100000_P04_POD-SKELETON_CAD (Autodesk Fusion 360 design; units mm, degrees)
description: POD - SPACESHIP (FocusPod v2) skeleton | Pod hoàn chỉnh
part number: 100000
description: BASE | Đế / sàn
part number: 110000
description: WALL | Vách
part number: 210000
description: FRONT | Mặt trước
part number: 350000
description: FRONT - DOOR AND GLAZING | Cửa và kính | P04
part number: 360000
description: CEILING | Trần
part number: 410000
description: LINING | Lớp tiêu âm
part number: 510000
description: AIR | Thông gió
part number: 610000
description: ELECTRICAL | Điện
part number: 710000
description: INTERIOR | Nội thất
part number: 810000
description: L1 WALL - SIDE PANEL - LOWER - LH | W-SIDE-LO | P04
part number: 2026-10-31-22-06-28-096
description: L1-CASS LINING - CASSETTE - SIDE LOWER - L | L-CASS-SIDE-LO | P04
part number: 2026-10-31-22-06-28-225
description: L2 WALL - SIDE PANEL - UPPER - LH | W-SIDE-UP | P04
part number: 2026-10-31-22-06-28-370
description: L2-CASS LINING - CASSETTE - SIDE UPPER - L | L-CASS-SIDE-UP | P04
part number: 2026-10-31-22-06-28-531
description: R1 WALL - SIDE PANEL - LOWER - RH | W-SIDE-LO | P04
part number: 2026-10-31-22-06-28-711
description: R1-CASS LINING - CASSETTE - SIDE LOWER - R | L-CASS-SIDE-LO | P04
part number: 2026-10-31-22-06-28-902
description: R2 WALL - SIDE PANEL - UPPER - RH | W-SIDE-UP | P04
part number: 2026-10-31-22-06-29-130
description: R2-CASS LINING - CASSETTE - SIDE UPPER - R | L-CASS-SIDE-UP | P04
part number: 2026-10-31-22-06-29-380
description: B1 WALL - BACK PANEL - LOWER - B1 | W-BACK-LO | P04
part number: 2026-10-31-22-06-29-641
description: B1-CASS LINING - CASSETTE - BACK LOWER - B1 | L-CASS-BACK-LO | P04
part number: 2026-10-31-22-06-29-889
description: B2 WALL - BACK PANEL - LOWER - B2 | W-BACK-LO | P04
part number: 2026-10-31-22-06-30-154
description: B2-CASS LINING - CASSETTE - BACK LOWER - B2 | L-CASS-BACK-LO | P04
part number: 2026-10-31-22-06-30-456
description: B3 WALL - BACK PANEL - UPPER - B3 | W-BACK-UP | P04
part number: 2026-10-31-22-06-30-798
description: B3-CASS LINING - CASSETTE - BACK UPPER - B3 | L-CASS-BACK-UP | P04
part number: 2026-10-31-22-06-31-178
description: B4 WALL - BACK PANEL - UPPER - B4 | W-BACK-UP | P04
part number: 2026-10-31-22-06-31-579
description: B4-CASS LINING - CASSETTE - BACK UPPER - B4 | L-CASS-BACK-UP | P04
part number: 2026-10-31-22-06-32-006
description: C1 CEILING - HALF PANEL - C1 | C-HALF | P04
part number: 2026-10-31-22-06-32-419
description: C1-CASS LINING - CASSETTE - CEILING - C1 | L-CASS-HALF | P04
part number: 2026-10-31-22-06-32-893
description: C2 CEILING - HALF PANEL - C2 | C-HALF | P04
part number: 2026-10-31-22-06-33-783
description: C2-CASS LINING - CASSETTE - CEILING - C2 | L-CASS-HALF | P04
part number: 2026-10-31-22-06-34-218
description: BAND-BACK BASE - BASE BAND - BACK | B-BAND-BACK | P04
part number: 2026-10-31-22-06-35-068
description: KICK FRONT - DOOR KICK STRIP | D-40 | P04
part number: 2026-10-31-22-06-36-171
description: DL FRONT - DECOR BLOCK - LEFT (FACETED, v1 MEASURED) | F-DL | P04
part number: 2026-10-31-22-06-36-706
description: DT FRONT - DECOR BLOCK - TOP (FACETED, v1 MEASURED) | F-DT | P04
part number: 2026-10-31-22-06-38-220
description: DR FRONT - DECOR BLOCK - RIGHT (FACETED, v1 MEASURED) | F-DR | P04
part number: 2026-10-31-22-06-40-806
description: DOOR FRONT - DOOR LEAF GLASS 4+4 (TRAPEZOID, v1 MEASURED) | F-GLASS-DOOR | P04
part number: 2026-10-31-22-06-44-745
description: FIXED FRONT - FIXED GLASS 4+4 (PENTAGON, v1 MEASURED) | F-GLASS-FIXED | P04
part number: 2026-10-31-22-06-45-730
description: BAND-L BASE - BASE BAND - SIDE - LH | B-BAND-SIDE | P04
part number: 2026-10-31-22-06-46-926
description: BAND-FL BASE - BASE BAND - FRONT LEFT (FACETED, UNDER DL) | B-BAND-FRONT | P04
part number: 2026-10-31-22-06-47-718
description: BAND-FR BASE - BASE BAND - FRONT RIGHT (FACETED, UNDER THE FIXED GLASS AND DR) | B-BAND-FRONT | P04
part number: 2026-10-31-22-06-49-290
description: BAND-R BASE - BASE BAND - SIDE - RH | B-BAND-SIDE | P04
part number: 2026-10-31-22-06-50-542
Autodesk Fusion 360 part; units mm, degrees
(part 1 of 2)
ref_plane "WorkPlane1" through (0, 0, 112.26) normal (0, 0, 1) x (1, 0, 0) in component "L1 WALL - SIDE PANEL - LOWER - LH"
sketch "OUTLINE - L1" plane through (0, 0, 112.26) normal (0, 0, 1) x (1, 0, 0) in component "L1 WALL - SIDE PANEL - LOWER - LH"
  line L0 (-1250, -642.74) -> (-1204, -642.74)
  line L1 (-1204, -642.74) -> (-1204, 850)
  line L2 (-1204, 850) -> (-1250, 850)
  line L3 (-1250, 850) -> (-1250, -642.74)
  dimension "d68" = 46
  dimension "d69" = 1492.74
  dimension "d70" = 1250
  dimension "d71" = 642.74
  constraint horizontal L0
  constraint vertical L1
  constraint horizontal L2
  constraint vertical L3
  measures "d68" horizontal distance of L0.start L0.end
  measures "d69" vertical distance of L0.start L2.end
  measures "d70" horizontal distance of origin L0.start
  measures "d71" vertical distance of origin L0.start
extrude "EXTRUDE - L1 ENVELOPE" add sketch "OUTLINE - L1" along normal blind 1142.74 makes body 1 in component "L1 WALL - SIDE PANEL - LOWER - LH"
ref_plane "WorkPlane1" through (0, 0, 112.26) normal (0, 0, 1) x (1, 0, 0) in component "L1-CASS LINING - CASSETTE - SIDE LOWER - L"
sketch "OUTLINE - L1-CASS" plane through (0, 0, 112.26) normal (0, 0, 1) x (1, 0, 0) in component "L1-CASS LINING - CASSETTE - SIDE LOWER - L"
  line L0 (-1200, -645) -> (-1166, -645)
  line L1 (-1166, -645) -> (-1166, 800)
  line L2 (-1166, 800) -> (-1200, 800)
  line L3 (-1200, 800) -> (-1200, -645)
  dimension "d76" = 34
  dimension "d77" = 1445
  dimension "d78" = 1200
  dimension "d79" = 645
  constraint horizontal L0
  constraint vertical L1
  constraint horizontal L2
  constraint vertical L3
  measures "d76" horizontal distance of L0.start L0.end
  measures "d77" vertical distance of L0.start L2.end
  measures "d78" horizontal distance of origin L0.start
  measures "d79" vertical distance of origin L0.start
extrude "EXTRUDE - L1-CASS ENVELOPE" add sketch "OUTLINE - L1-CASS" along normal blind 1142.74 separate body makes body 2 in component "L1-CASS LINING - CASSETTE - SIDE LOWER - L"
ref_plane "WorkPlane1" through (0, 0, 1257.26) normal (0, 0, 1) x (1, 0, 0) in component "L2 WALL - SIDE PANEL - UPPER - LH"
sketch "OUTLINE - L2" plane through (0, 0, 1257.26) normal (0, 0, 1) x (1, 0, 0) in component "L2 WALL - SIDE PANEL - UPPER - LH"
  line L0 (-1250, -642.74) -> (-1204, -642.74)
  line L1 (-1204, -642.74) -> (-1204, 850)
  line L2 (-1204, 850) -> (-1250, 850)
  line L3 (-1250, 850) -> (-1250, -642.74)
  dimension "d84" = 46
  dimension "d85" = 1492.74
  dimension "d86" = 1250
  dimension "d87" = 642.74
  constraint horizontal L0
  constraint vertical L1
  constraint horizontal L2
  constraint vertical L3
  measures "d84" horizontal distance of L0.start L0.end
  measures "d85" vertical distance of L0.start L2.end
  measures "d86" horizontal distance of origin L0.start
  measures "d87" vertical distance of origin L0.start
extrude "EXTRUDE - L2 ENVELOPE" add sketch "OUTLINE - L2" along normal blind 1142.74 separate body makes body 3 in component "L2 WALL - SIDE PANEL - UPPER - LH"
ref_plane "WorkPlane1" through (0, 0, 1257.26) normal (0, 0, 1) x (1, 0, 0) in component "L2-CASS LINING - CASSETTE - SIDE UPPER - L"
sketch "OUTLINE - L2-CASS" plane through (0, 0, 1257.26) normal (0, 0, 1) x (1, 0, 0) in component "L2-CASS LINING - CASSETTE - SIDE UPPER - L"
  line L0 (-1200, -645) -> (-1166, -645)
  line L1 (-1166, -645) -> (-1166, 800)
  line L2 (-1166, 800) -> (-1200, 800)
  line L3 (-1200, 800) -> (-1200, -645)
  dimension "d92" = 34
  dimension "d93" = 1445
  dimension "d94" = 1200
  dimension "d95" = 645
  constraint horizontal L0
  constraint vertical L1
  constraint horizontal L2
  constraint vertical L3
  measures "d92" horizontal distance of L0.start L0.end
  measures "d93" vertical distance of L0.start L2.end
  measures "d94" horizontal distance of origin L0.start
  measures "d95" vertical distance of origin L0.start
extrude "EXTRUDE - L2-CASS ENVELOPE" add sketch "OUTLINE - L2-CASS" along normal blind 1092.74 separate body makes body 4 in component "L2-CASS LINING - CASSETTE - SIDE UPPER - L"
ref_plane "WorkPlane1" through (0, 0, 112.26) normal (0, 0, 1) x (1, 0, 0) in component "R1 WALL - SIDE PANEL - LOWER - RH"
sketch "OUTLINE - R1" plane through (0, 0, 112.26) normal (0, 0, 1) x (1, 0, 0) in component "R1 WALL - SIDE PANEL - LOWER - RH"
  line L0 (1204, -642.74) -> (1250, -642.74)
  line L1 (1250, -642.74) -> (1250, 850)
  line L2 (1250, 850) -> (1204, 850)
  line L3 (1204, 850) -> (1204, -642.74)
  dimension "d100" = 46
  dimension "d101" = 1492.74
  dimension "d102" = 1204
  dimension "d103" = 642.74
  constraint horizontal L0
  constraint vertical L1
  constraint horizontal L2
  constraint vertical L3
  measures "d100" horizontal distance of L0.start L0.end
  measures "d101" vertical distance of L0.start L2.end
  measures "d102" horizontal distance of origin L0.start
  measures "d103" vertical distance of origin L0.start
extrude "EXTRUDE - R1 ENVELOPE" add sketch "OUTLINE - R1" along normal blind 1142.74 separate body makes body 5 in component "R1 WALL - SIDE PANEL - LOWER - RH"
ref_plane "WorkPlane1" through (0, 0, 112.26) normal (0, 0, 1) x (1, 0, 0) in component "R1-CASS LINING - CASSETTE - SIDE LOWER - R"
sketch "OUTLINE - R1-CASS" plane through (0, 0, 112.26) normal (0, 0, 1) x (1, 0, 0) in component "R1-CASS LINING - CASSETTE - SIDE LOWER - R"
  line L0 (1166, -645) -> (1200, -645)
  line L1 (1200, -645) -> (1200, 800)
  line L2 (1200, 800) -> (1166, 800)
  line L3 (1166, 800) -> (1166, -645)
  dimension "d108" = 34
  dimension "d109" = 1445
  dimension "d110" = 1166
  dimension "d111" = 645
  constraint horizontal L0
  constraint vertical L1
  constraint horizontal L2
  constraint vertical L3
  measures "d108" horizontal distance of L0.start L0.end
  measures "d109" vertical distance of L0.start L2.end
  measures "d110" horizontal distance of origin L0.start
  measures "d111" vertical distance of origin L0.start
extrude "EXTRUDE - R1-CASS ENVELOPE" add sketch "OUTLINE - R1-CASS" along normal blind 1142.74 separate body makes body 6 in component "R1-CASS LINING - CASSETTE - SIDE LOWER - R"
ref_plane "WorkPlane1" through (0, 0, 1257.26) normal (0, 0, 1) x (1, 0, 0) in component "R2 WALL - SIDE PANEL - UPPER - RH"
sketch "OUTLINE - R2" plane through (0, 0, 1257.26) normal (0, 0, 1) x (1, 0, 0) in component "R2 WALL - SIDE PANEL - UPPER - RH"
  line L0 (1204, -642.74) -> (1250, -642.74)
  line L1 (1250, -642.74) -> (1250, 850)
  line L2 (1250, 850) -> (1204, 850)
  line L3 (1204, 850) -> (1204, -642.74)
  dimension "d116" = 46
  dimension "d117" = 1492.74
  dimension "d118" = 1204
  dimension "d119" = 642.74
  constraint horizontal L0
  constraint vertical L1
  constraint horizontal L2
  constraint vertical L3
  measures "d116" horizontal distance of L0.start L0.end
  measures "d117" vertical distance of L0.start L2.end
  measures "d118" horizontal distance of origin L0.start
  measures "d119" vertical distance of origin L0.start
extrude "EXTRUDE - R2 ENVELOPE" add sketch "OUTLINE - R2" along normal blind 1142.74 separate body makes body 7 in component "R2 WALL - SIDE PANEL - UPPER - RH"
ref_plane "WorkPlane1" through (0, 0, 1257.26) normal (0, 0, 1) x (1, 0, 0) in component "R2-CASS LINING - CASSETTE - SIDE UPPER - R"
sketch "OUTLINE - R2-CASS" plane through (0, 0, 1257.26) normal (0, 0, 1) x (1, 0, 0) in component "R2-CASS LINING - CASSETTE - SIDE UPPER - R"
  line L0 (1166, -645) -> (1200, -645)
  line L1 (1200, -645) -> (1200, 800)
  line L2 (1200, 800) -> (1166, 800)
  line L3 (1166, 800) -> (1166, -645)
  dimension "d124" = 34
  dimension "d125" = 1445
  dimension "d126" = 1166
  dimension "d127" = 645
  constraint horizontal L0
  constraint vertical L1
  constraint horizontal L2
  constraint vertical L3
  measures "d124" horizontal distance of L0.start L0.end
  measures "d125" vertical distance of L0.start L2.end
  measures "d126" horizontal distance of origin L0.start
  measures "d127" vertical distance of origin L0.start
extrude "EXTRUDE - R2-CASS ENVELOPE" add sketch "OUTLINE - R2-CASS" along normal blind 1092.74 separate body makes body 8 in component "R2-CASS LINING - CASSETTE - SIDE UPPER - R"
ref_plane "WorkPlane1" through (0, 0, 112.26) normal (0, 0, 1) x (1, 0, 0) in component "B1 WALL - BACK PANEL - LOWER - B1"
sketch "OUTLINE - B1" plane through (0, 0, 112.26) normal (0, 0, 1) x (1, 0, 0) in component "B1 WALL - BACK PANEL - LOWER - B1"
  line L0 (-1201.74, 804) -> (-1.13, 804)
  line L1 (-1.13, 804) -> (-1.13, 850)
  line L2 (-1.13, 850) -> (-1201.74, 850)
  line L3 (-1201.74, 850) -> (-1201.74, 804)
  dimension "d132" = 1200.61
  dimension "d133" = 46
  dimension "d134" = 1201.74
  dimension "d135" = 804
  constraint horizontal L0
  constraint vertical L1
  constraint horizontal L2
  constraint vertical L3
  measures "d132" horizontal distance of L0.start L0.end
  measures "d133" vertical distance of L0.start L2.end
  measures "d134" horizontal distance of origin L0.start
  measures "d135" vertical distance of origin L0.start
extrude "EXTRUDE - B1 ENVELOPE" add sketch "OUTLINE - B1" along normal blind 1118.61 separate body makes body 9 in component "B1 WALL - BACK PANEL - LOWER - B1"
ref_plane "WorkPlane1" through (0, 0, 112.26) normal (0, 0, 1) x (1, 0, 0) in component "B1-CASS LINING - CASSETTE - BACK LOWER - B1"
sketch "OUTLINE - B1-CASS" plane through (0, 0, 112.26) normal (0, 0, 1) x (1, 0, 0) in component "B1-CASS LINING - CASSETTE - BACK LOWER - B1"
  line L0 (-1166, 766) -> (0, 766)
  line L1 (0, 766) -> (0, 800)
  line L2 (0, 800) -> (-1166, 800)
  line L3 (-1166, 800) -> (-1166, 766)
  dimension "d140" = 1166
  dimension "d141" = 34
  dimension "d142" = 1166
  dimension "d143" = 766
  constraint horizontal L0
  constraint vertical L1
  constraint horizontal L2
  constraint vertical L3
  measures "d140" horizontal distance of L0.start L0.end
  measures "d141" vertical distance of L0.start L2.end
  measures "d142" horizontal distance of origin L0.start
  measures "d143" vertical distance of origin L0.start
extrude "EXTRUDE - B1-CASS ENVELOPE" add sketch "OUTLINE - B1-CASS" along normal blind 1118.61 separate body makes body 10 in component "B1-CASS LINING - CASSETTE - BACK LOWER - B1"
ref_plane "WorkPlane1" through (0, 0, 112.26) normal (0, 0, 1) x (1, 0, 0) in component "B2 WALL - BACK PANEL - LOWER - B2"
sketch "OUTLINE - B2" plane through (0, 0, 112.26) normal (0, 0, 1) x (1, 0, 0) in component "B2 WALL - BACK PANEL - LOWER - B2"
  line L0 (1.13, 804) -> (1201.74, 804)
  line L1 (1201.74, 804) -> (1201.74, 850)
  line L2 (1201.74, 850) -> (1.13, 850)
  line L3 (1.13, 850) -> (1.13, 804)
  dimension "d148" = 1200.61
  dimension "d149" = 46
  dimension "d150" = 1.13
  dimension "d151" = 804
  constraint horizontal L0
  constraint vertical L1
  constraint horizontal L2
  constraint vertical L3
  measures "d148" horizontal distance of L0.start L0.end
  measures "d149" vertical distance of L0.start L2.end
  measures "d150" horizontal distance of origin L0.start
  measures "d151" vertical distance of origin L0.start
extrude "EXTRUDE - B2 ENVELOPE" add sketch "OUTLINE - B2" along normal blind 1118.61 separate body makes body 11 in component "B2 WALL - BACK PANEL - LOWER - B2"
ref_plane "WorkPlane1" through (0, 0, 112.26) normal (0, 0, 1) x (1, 0, 0) in component "B2-CASS LINING - CASSETTE - BACK LOWER - B2"
sketch "OUTLINE - B2-CASS" plane through (0, 0, 112.26) normal (0, 0, 1) x (1, 0, 0) in component "B2-CASS LINING - CASSETTE - BACK LOWER - B2"
  line L0 (0, 766) -> (1166, 766)
  line L1 (1166, 766) -> (1166, 800)
  line L2 (1166, 800) -> (0, 800)
  line L3 (0, 800) -> (0, 766)
  dimension "d156" = 1166
  dimension "d157" = 34
  dimension "d158" = 766
  constraint horizontal L0
  constraint vertical L1
  constraint horizontal L2
  constraint vertical L3
  constraint vertical origin L0.start
  measures "d156" horizontal distance of L0.start L0.end
  measures "d157" vertical distance of L0.start L2.end
  measures "d158" vertical distance of origin L0.start
extrude "EXTRUDE - B2-CASS ENVELOPE" add sketch "OUTLINE - B2-CASS" along normal blind 1118.61 separate body makes body 12 in component "B2-CASS LINING - CASSETTE - BACK LOWER - B2"
ref_plane "WorkPlane1" through (0, 0, 1233.13) normal (0, 0, 1) x (1, 0, 0) in component "B3 WALL - BACK PANEL - UPPER - B3"
sketch "OUTLINE - B3" plane through (0, 0, 1233.13) normal (0, 0, 1) x (1, 0, 0) in component "B3 WALL - BACK PANEL - UPPER - B3"
  line L0 (-1201.74, 804) -> (-1.13, 804)
  line L1 (-1.13, 804) -> (-1.13, 850)
  line L2 (-1.13, 850) -> (-1201.74, 850)
  line L3 (-1201.74, 850) -> (-1201.74, 804)
  dimension "d163" = 1200.61
  dimension "d164" = 46
  dimension "d165" = 1201.74
  dimension "d166" = 804
  constraint horizontal L0
  constraint vertical L1
  constraint horizontal L2
  constraint vertical L3
  measures "d163" horizontal distance of L0.start L0.end
  measures "d164" vertical distance of L0.start L2.end
  measures "d165" horizontal distance of origin L0.start
  measures "d166" vertical distance of origin L0.start
extrude "EXTRUDE - B3 ENVELOPE" add sketch "OUTLINE - B3" along normal blind 1118.61 separate body makes body 13 in component "B3 WALL - BACK PANEL - UPPER - B3"
ref_plane "WorkPlane1" through (0, 0, 1233.13) normal (0, 0, 1) x (1, 0, 0) in component "B3-CASS LINING - CASSETTE - BACK UPPER - B3"
sketch "OUTLINE - B3-CASS" plane through (0, 0, 1233.13) normal (0, 0, 1) x (1, 0, 0) in component "B3-CASS LINING - CASSETTE - BACK UPPER - B3"
  line L0 (-1166, 766) -> (0, 766)
  line L1 (0, 766) -> (0, 800)
  line L2 (0, 800) -> (-1166, 800)
  line L3 (-1166, 800) -> (-1166, 766)
  dimension "d171" = 1166
  dimension "d172" = 34
  dimension "d173" = 1166
  dimension "d174" = 766
  constraint horizontal L0
  constraint vertical L1
  constraint horizontal L2
  constraint vertical L3
  measures "d171" horizontal distance of L0.start L0.end
  measures "d172" vertical distance of L0.start L2.end
  measures "d173" horizontal distance of origin L0.start
  measures "d174" vertical distance of origin L0.start
extrude "EXTRUDE - B3-CASS ENVELOPE" add sketch "OUTLINE - B3-CASS" along normal blind 1116.87 separate body makes body 14 in component "B3-CASS LINING - CASSETTE - BACK UPPER - B3"
ref_plane "WorkPlane1" through (0, 0, 1233.13) normal (0, 0, 1) x (1, 0, 0) in component "B4 WALL - BACK PANEL - UPPER - B4"
sketch "OUTLINE - B4" plane through (0, 0, 1233.13) normal (0, 0, 1) x (1, 0, 0) in component "B4 WALL - BACK PANEL - UPPER - B4"
  line L0 (1.13, 804) -> (1201.74, 804)
  line L1 (1201.74, 804) -> (1201.74, 850)
  line L2 (1201.74, 850) -> (1.13, 850)
  line L3 (1.13, 850) -> (1.13, 804)
  dimension "d179" = 1200.61
  dimension "d180" = 46
  dimension "d181" = 1.13
  dimension "d182" = 804
  constraint horizontal L0
  constraint vertical L1
  constraint horizontal L2
  constraint vertical L3
  measures "d179" horizontal distance of L0.start L0.end
  measures "d180" vertical distance of L0.start L2.end
  measures "d181" horizontal distance of origin L0.start
  measures "d182" vertical distance of origin L0.start
extrude "EXTRUDE - B4 ENVELOPE" add sketch "OUTLINE - B4" along normal blind 1118.61 separate body makes body 15 in component "B4 WALL - BACK PANEL - UPPER - B4"
ref_plane "WorkPlane1" through (0, 0, 1233.13) normal (0, 0, 1) x (1, 0, 0) in component "B4-CASS LINING - CASSETTE - BACK UPPER - B4"
sketch "OUTLINE - B4-CASS" plane through (0, 0, 1233.13) normal (0, 0, 1) x (1, 0, 0) in component "B4-CASS LINING - CASSETTE - BACK UPPER - B4"
  line L0 (0, 766) -> (1166, 766)
  line L1 (1166, 766) -> (1166, 800)
  line L2 (1166, 800) -> (0, 800)
  line L3 (0, 800) -> (0, 766)
  dimension "d187" = 1166
  dimension "d188" = 34
  dimension "d189" = 766
  constraint horizontal L0
  constraint vertical L1
  constraint horizontal L2
  constraint vertical L3
  constraint vertical origin L0.start
  measures "d187" horizontal distance of L0.start L0.end
  measures "d188" vertical distance of L0.start L2.end
  measures "d189" vertical distance of origin L0.start
extrude "EXTRUDE - B4-CASS ENVELOPE" add sketch "OUTLINE - B4-CASS" along normal blind 1116.87 separate body makes body 16 in component "B4-CASS LINING - CASSETTE - BACK UPPER - B4"
ref_plane "WorkPlane1" through (0, 0, 2354) normal (0, 0, 1) x (1, 0, 0) in component "C1 CEILING - HALF PANEL - C1"
sketch "OUTLINE - C1" plane through (0, 0, 2354) normal (0, 0, 1) x (1, 0, 0) in component "C1 CEILING - HALF PANEL - C1"
  line L0 (-1201.74, -645) -> (-1.13, -645)
  line L1 (-1.13, -645) -> (-1.13, 850)
  line L2 (-1.13, 850) -> (-1201.74, 850)
  line L3 (-1201.74, 850) -> (-1201.74, -645)
  dimension "d194" = 1200.61
  dimension "d195" = 1495
  dimension "d196" = 1201.74
  dimension "d197" = 645
  constraint horizontal L0
  constraint vertical L1
  constraint horizontal L2
  constraint vertical L3
  measures "d194" horizontal distance of L0.start L0.end
  measures "d195" vertical distance of L0.start L2.end
  measures "d196" horizontal distance of origin L0.start
  measures "d197" vertical distance of origin L0.start
extrude "EXTRUDE - C1 ENVELOPE" add sketch "OUTLINE - C1" along normal blind 46 separate body makes body 17 in component "C1 CEILING - HALF PANEL - C1"
ref_plane "WorkPlane1" through (0, 0, 2316) normal (0, 0, 1) x (1, 0, 0) in component "C1-CASS LINING - CASSETTE - CEILING - C1"
sketch "OUTLINE - C1-CASS" plane through (0, 0, 2316) normal (0, 0, 1) x (1, 0, 0) in component "C1-CASS LINING - CASSETTE - CEILING - C1"
  line L0 (-1166, -645) -> (0, -645)
  line L1 (0, -645) -> (0, 766)
  line L2 (0, 766) -> (-1166, 766)
  line L3 (-1166, 766) -> (-1166, -645)
  dimension "d202" = 1166
  dimension "d203" = 1411
  dimension "d204" = 1166
  dimension "d205" = 645
  constraint horizontal L0
  constraint vertical L1
  constraint horizontal L2
  constraint vertical L3
  measures "d202" horizontal distance of L0.start L0.end
  measures "d203" vertical distance of L0.start L2.end
  measures "d204" horizontal distance of origin L0.start
  measures "d205" vertical distance of origin L0.start
extrude "EXTRUDE - C1-CASS ENVELOPE" add sketch "OUTLINE - C1-CASS" along normal blind 34 separate body makes body 18 in component "C1-CASS LINING - CASSETTE - CEILING - C1"
ref_plane "WorkPlane1" through (0, 0, 2354) normal (0, 0, 1) x (1, 0, 0) in component "C2 CEILING - HALF PANEL - C2"
sketch "OUTLINE - C2" plane through (0, 0, 2354) normal (0, 0, 1) x (1, 0, 0) in component "C2 CEILING - HALF PANEL - C2"
  line L0 (1.13, -645) -> (1201.74, -645)
  line L1 (1201.74, -645) -> (1201.74, 850)
  line L2 (1201.74, 850) -> (1.13, 850)
  line L3 (1.13, 850) -> (1.13, -645)
  dimension "d216" = 1200.61
  dimension "d217" = 1495
  dimension "d218" = 1.13
  dimension "d219" = 645
  constraint horizontal L0
  constraint vertical L1
  constraint horizontal L2
  constraint vertical L3
  measures "d216" horizontal distance of L0.start L0.end
  measures "d217" vertical distance of L0.start L2.end
  measures "d218" horizontal distance of origin L0.start
  measures "d219" vertical distance of origin L0.start
extrude "EXTRUDE - C2 ENVELOPE" add sketch "OUTLINE - C2" along normal blind 46 separate body makes body 19 in component "C2 CEILING - HALF PANEL - C2"
ref_plane "WorkPlane1" through (0, 0, 2316) normal (0, 0, 1) x (1, 0, 0) in component "C2-CASS LINING - CASSETTE - CEILING - C2"
sketch "OUTLINE - C2-CASS" plane through (0, 0, 2316) normal (0, 0, 1) x (1, 0, 0) in component "C2-CASS LINING - CASSETTE - CEILING - C2"
  line L0 (0, -645) -> (1166, -645)
  line L1 (1166, -645) -> (1166, 766)
  line L2 (1166, 766) -> (0, 766)
  line L3 (0, 766) -> (0, -645)
  dimension "d224" = 1166
  dimension "d225" = 1411
  dimension "d226" = 645
  constraint horizontal L0
  constraint vertical L1
  constraint horizontal L2
  constraint vertical L3
  constraint vertical origin L0.start
  measures "d224" horizontal distance of L0.start L0.end
  measures "d225" vertical distance of L0.start L2.end
  measures "d226" vertical distance of origin L0.start
extrude "EXTRUDE - C2-CASS ENVELOPE" add sketch "OUTLINE - C2-CASS" along normal blind 34 separate body makes body 20 in component "C2-CASS LINING - CASSETTE - CEILING - C2"
ref_plane "WorkPlane1" through (0, 0, 10) normal (0, 0, 1) x (1, 0, 0) in component "BAND-BACK BASE - BASE BAND - BACK"
sketch "OUTLINE - BAND-BACK" plane through (0, 0, 10) normal (0, 0, 1) x (1, 0, 0) in component "BAND-BACK BASE - BASE BAND - BACK"
  line L0 (-1210, 810) -> (1210, 810)
  line L1 (1210, 810) -> (1210, 850)
  line L2 (1210, 850) -> (-1210, 850)
  line L3 (-1210, 850) -> (-1210, 810)
  dimension "d236" = 2420
  dimension "d237" = 40
  dimension "d238" = 1210
  dimension "d239" = 810
  constraint horizontal L0
  constraint vertical L1
  constraint horizontal L2
  constraint vertical L3
  measures "d236" horizontal distance of L0.start L0.end
  measures "d237" vertical distance of L0.start L2.end
  measures "d238" horizontal distance of origin L0.start
  measures "d239" vertical distance of origin L0.start
extrude "EXTRUDE - BAND-BACK ENVELOPE" add sketch "OUTLINE - BAND-BACK" along normal blind 100 separate body makes body 21 in component "BAND-BACK BASE - BASE BAND - BACK"
ref_plane "WorkPlane1" through (0, 0, 10) normal (0, 0, 1) x (1, 0, 0) in component "KICK FRONT - DOOR KICK STRIP"
sketch "OUTLINE - KICK" plane through (0, 0, 10) normal (0, 0, 1) x (1, 0, 0) in component "KICK FRONT - DOOR KICK STRIP"
  line L0 (-961, -709) -> (214, -709)
  line L1 (214, -709) -> (214, -689)
  line L2 (214, -689) -> (-961, -689)
  line L3 (-961, -689) -> (-961, -709)
  dimension "d250" = 1175
  dimension "d251" = 20
  dimension "d252" = 961
  dimension "d253" = 709
  constraint horizontal L0
  constraint vertical L1
  constraint horizontal L2
  constraint vertical L3
  measures "d250" horizontal distance of L0.start L0.end
  measures "d251" vertical distance of L0.start L2.end
  measures "d252" horizontal distance of origin L0.start
  measures "d253" vertical distance of origin L0.start
extrude "EXTRUDE - KICK ENVELOPE" add sketch "OUTLINE - KICK" along normal blind 95 separate body makes body 22 in component "KICK FRONT - DOOR KICK STRIP"
sketch "PLAN - DL FACETS" plane through (0, 0, 0) normal (0, 0, 1) x (1, 0, 0) in component "DL FRONT - DECOR BLOCK - LEFT (FACETED, v1 MEASURED)"
  line L0 (-1250, -645) -> (-1250, -670)
  line L1 (-1250, -670) -> (-1158, -752)
  line L2 (-1158, -752) -> (-979, -844)
  line L3 (-979, -844) -> (-972, -844)
  line L4 (-972, -844) -> (-972, -645)
  line L5 (-972, -645) -> (-1250, -645)
  dimension "d256" = 1250
  dimension "d257" = 1158
  dimension "d258" = 979
  dimension "d259" = 972
  dimension "d260" = 670
  dimension "d261" = 752
  dimension "d262" = 844
  dimension "d263" = 645
  constraint vertical L0
  constraint vertical L4
  constraint horizontal L3
  constraint horizontal L5
  measures "d256" horizontal distance of origin L0.start
  measures "d257" horizontal distance of origin L1.end
  measures "d258" horizontal distance of origin L2.end
  measures "d259" horizontal distance of origin L3.end
  measures "d260" vertical distance of origin L0.end
  measures "d261" vertical distance of origin L1.end
  measures "d262" vertical distance of origin L2.end
  measures "d263" vertical distance of origin L4.end
extrude "EXTRUDE - DL PLAN" add sketch "PLAN - DL FACETS" along normal blind 2290 from surface at 110 separate body makes body 23 in component "DL FRONT - DECOR BLOCK - LEFT (FACETED, v1 MEASURED)"
sketch "SLOPE - DL TOP" plane through (0, 0, 0) normal (0, 1, 0) x (1, 0, 0) in component "DL FRONT - DECOR BLOCK - LEFT (FACETED, v1 MEASURED)"
  line L0 (-1250, -2397) -> (-972, -2120)
  line L1 (-972, -2120) -> (-972, -2400)
  line L2 (-972, -2400) -> (-1250, -2400)
  line L3 (-1250, -2400) -> (-1250, -2397)
  dimension "d267" = 972
  dimension "d268" = 1250
  dimension "d269" = 2397
  dimension "d270" = 2120
  dimension "d271" = 2400
  constraint vertical L1
  constraint vertical L3
  constraint horizontal L2
  measures "d267" horizontal distance of origin L0.end
  measures "d268" horizontal distance of origin L2.end
  measures "d269" vertical distance of origin L0.start
  measures "d270" vertical distance of origin L0.end
  measures "d271" vertical distance of origin L1.end
extrude "CUT - DL TOP SLOPE" cut sketch "SLOPE - DL TOP" along normal blind 205 from surface at -850 bodies 23 in component "DL FRONT - DECOR BLOCK - LEFT (FACETED, v1 MEASURED)"
sketch "PLAN - DT FACETS" plane through (0, 0, 0) normal (0, 0, 1) x (1, 0, 0) in component "DT FRONT - DECOR BLOCK - TOP (FACETED, v1 MEASURED)"
  line L0 (-1250, -645) -> (-1250, -670)
  line L1 (-1250, -670) -> (-1154, -753)
  line L2 (-1154, -753) -> (-969, -767)
  line L3 (-969, -767) -> (230, -850)
  line L4 (230, -850) -> (449, -672)
  line L5 (449, -672) -> (449, -645)
  line L6 (449, -645) -> (-1250, -645)
  dimension "d275" = 1250
  dimension "d276" = 1154
  dimension "d277" = 969
  dimension "d278" = 230
  dimension "d279" = 449
  dimension "d280" = 670
  dimension "d281" = 753
  dimension "d282" = 767
  dimension "d283" = 850
  dimension "d284" = 672
  dimension "d285" = 645
  constraint vertical L0
  constraint vertical L5
  constraint horizontal L6
  measures "d275" horizontal distance of origin L0.start
  measures "d276" horizontal distance of origin L1.end
  measures "d277" horizontal distance of origin L2.end
  measures "d278" horizontal distance of origin L3.end
  measures "d279" horizontal distance of origin L4.end
  measures "d280" vertical distance of origin L0.end
  measures "d281" vertical distance of origin L1.end
  measures "d282" vertical distance of origin L2.end
  measures "d283" vertical distance of origin L3.end
  measures "d284" vertical distance of origin L4.end
  measures "d285" vertical distance of origin L5.end
extrude "EXTRUDE - DT PLAN" add sketch "PLAN - DT FACETS" along normal blind 280 from surface at 2120 separate body makes body 24 in component "DT FRONT - DECOR BLOCK - TOP (FACETED, v1 MEASURED)"
sketch "SLOPE - DT BOTTOM" plane through (0, 0, 0) normal (0, 1, 0) x (1, 0, 0) in component "DT FRONT - DECOR BLOCK - TOP (FACETED, v1 MEASURED)"
  line L0 (-1250, -2120) -> (-972, -2120)
  line L1 (-972, -2120) -> (-1250, -2397)
  line L2 (-1250, -2397) -> (-1250, -2120)
  dimension "d289" = 972
  dimension "d290" = 1250
  dimension "d291" = 2120
  dimension "d292" = 2397
  constraint vertical L2
  constraint horizontal L0
  measures "d289" horizontal distance of origin L0.end
  measures "d290" horizontal distance of origin L1.end
  measures "d291" vertical distance of origin L0.start
  measures "d292" vertical distance of origin L1.end
extrude "CUT - DT BOTTOM SLOPE" cut sketch "SLOPE - DT BOTTOM" along normal blind 205 from surface at -850 bodies 24 in component "DT FRONT - DECOR BLOCK - TOP (FACETED, v1 MEASURED)"
sketch "CHAMFER - DT TOP FRONT" plane through (0, 0, 0) normal (1, 0, 0) x (0, 0, -1) in component "DT FRONT - DECOR BLOCK - TOP (FACETED, v1 MEASURED)"
  line L0 (-2200, -850) -> (-2400, -672)
  line L1 (-2400, -672) -> (-2400, -850)
  line L2 (-2400, -850) -> (-2200, -850)
  dimension "d296" = 2200
  dimension "d297" = 2400
  dimension "d298" = 672
  dimension "d299" = 850
  constraint vertical L1
  constraint horizontal L2
  measures "d296" horizontal distance of origin L0.start
  measures "d297" horizontal distance of origin L0.end
  measures "d298" vertical distance of origin L0.end
  measures "d299" vertical distance of origin L1.end
extrude "CUT - DT TOP CHAMFER" cut sketch "CHAMFER - DT TOP FRONT" along normal blind 2500 from surface at -1250 bodies 24 in component "DT FRONT - DECOR BLOCK - TOP (FACETED, v1 MEASURED)"
sketch "FRONT - DR OUTLINE" plane through (0, 0, 0) normal (0, 1, 0) x (1, 0, 0) in component "DR FRONT - DECOR BLOCK - RIGHT (FACETED, v1 MEASURED)"
  line L0 (948, -102) -> (1250, -102)
  line L1 (1250, -102) -> (1250, -2400)
  line L2 (1250, -2400) -> (230, -2400)
  line L3 (230, -2400) -> (230, -2120)
  line L4 (230, -2120) -> (749, -1521)
  line L5 (749, -1521) -> (948, -102)
  dimension "d303" = 948
  dimension "d304" = 1250
  dimension "d305" = 230
  dimension "d306" = 749
  dimension "d307" = 102
  dimension "d308" = 2400
  dimension "d309" = 2120
  dimension "d310" = 1521
  constraint vertical L1
  constraint vertical L3
  constraint horizontal L0
  constraint horizontal L2
  measures "d303" horizontal distance of origin L0.start
  measures "d304" horizontal distance of origin L0.end
  measures "d305" horizontal distance of origin L2.end
  measures "d306" horizontal distance of origin L4.end
  measures "d307" vertical distance of origin L0.start
  measures "d308" vertical distance of origin L1.end
  measures "d309" vertical distance of origin L3.end
  measures "d310" vertical distance of origin L4.end
extrude "EXTRUDE - DR OUTLINE" add sketch "FRONT - DR OUTLINE" along normal blind 205 from surface at -850 separate body makes body 25 in component "DR FRONT - DECOR BLOCK - RIGHT (FACETED, v1 MEASURED)"
sketch "CORNER FACET - DR" plane through (0, 0, 0) normal (0, 0, 1) x (1, 0, 0) in component "DR FRONT - DECOR BLOCK - RIGHT (FACETED, v1 MEASURED)"
  line L0 (1052, -850) -> (1250, -672)
  line L1 (1250, -672) -> (1250, -850)
  line L2 (1250, -850) -> (1052, -850)
  dimension "d314" = 1052
  dimension "d315" = 1250
  dimension "d316" = 672
  dimension "d317" = 850
  constraint vertical L1
  constraint horizontal L2
  measures "d314" horizontal distance of origin L0.start
  measures "d315" horizontal distance of origin L0.end
  measures "d316" vertical distance of origin L0.end
  measures "d317" vertical distance of origin L1.end
extrude "CUT - DR CORNER FACET" cut sketch "CORNER FACET - DR" along normal blind 2400 bodies 25 in component "DR FRONT - DECOR BLOCK - RIGHT (FACETED, v1 MEASURED)"
sketch "JOINT - DR TO DT (v1 LINE TO X 449)" plane through (0, 0, 0) normal (0, 0, 1) x (1, 0, 0) in component "DR FRONT - DECOR BLOCK - RIGHT (FACETED, v1 MEASURED)"
  line L0 (230, -850) -> (449, -672)
  line L1 (449, -672) -> (449, -645)
  line L2 (449, -645) -> (230, -645)
  line L3 (230, -645) -> (230, -850)
  dimension "d321" = 449
  dimension "d322" = 230
  dimension "d323" = 850
  dimension "d324" = 672
  dimension "d325" = 645
  constraint vertical L1
  constraint vertical L3
  constraint horizontal L2
  measures "d321" horizontal distance of origin L0.end
  measures "d322" horizontal distance of origin L2.end
  measures "d323" vertical distance of origin L0.start
  measures "d324" vertical distance of origin L0.end
  measures "d325" vertical distance of origin L1.end
extrude "CUT - DR TO DT JOINT" cut sketch "JOINT - DR TO DT (v1 LINE TO X 449)" along normal blind 280 from surface at 2120 bodies 25 in component "DR FRONT - DECOR BLOCK - RIGHT (FACETED, v1 MEASURED)"
sketch "CHAMFER - DR TOP FRONT" plane through (0, 0, 0) normal (1, 0, 0) x (0, 0, -1) in component "DR FRONT - DECOR BLOCK - RIGHT (FACETED, v1 MEASURED)"
  line L0 (-2200, -850) -> (-2400, -672)
  line L1 (-2400, -672) -> (-2400, -850)
  line L2 (-2400, -850) -> (-2200, -850)
  dimension "d329" = 2200
  dimension "d330" = 2400
  dimension "d331" = 672
  dimension "d332" = 850
  constraint vertical L1
  constraint horizontal L2
  measures "d329" horizontal distance of origin L0.start
  measures "d330" horizontal distance of origin L0.end
  measures "d331" vertical distance of origin L0.end
  measures "d332" vertical distance of origin L1.end
extrude "CUT - DR TOP CHAMFER" cut sketch "CHAMFER - DR TOP FRONT" along normal blind 2500 from surface at -1250 bodies 25 in component "DR FRONT - DECOR BLOCK - RIGHT (FACETED, v1 MEASURED)"
sketch "PLAN - DR BOTTOM ON THE BAND" plane through (0, 0, 0) normal (0, 0, 1) x (1, 0, 0) in component "DR FRONT - DECOR BLOCK - RIGHT (FACETED, v1 MEASURED)"
  line L0 (230, -850) -> (1250, -850)
  line L1 (1250, -850) -> (1250, -645)
  line L2 (1250, -645) -> (230, -645)
  line L3 (230, -645) -> (230, -850)
  dimension "d336" = 1250
  dimension "d337" = 230
  dimension "d338" = 850
  dimension "d339" = 645
  constraint vertical L1
  constraint vertical L3
  constraint horizontal L0
  constraint horizontal L2
  measures "d336" horizontal distance of origin L0.end
  measures "d337" horizontal distance of origin L2.end
  measures "d338" vertical distance of origin L0.start
  measures "d339" vertical distance of origin L1.end
extrude "CUT - DR BOTTOM AT THE BASE BAND TOP" cut sketch "PLAN - DR BOTTOM ON THE BAND" along normal blind 110 bodies 25 in component "DR FRONT - DECOR BLOCK - RIGHT (FACETED, v1 MEASURED)"
sketch "OUTLINE - DOOR" plane through (0, 0, 0) normal (0, 1, 0) x (1, 0, 0) in component "DOOR FRONT - DOOR LEAF GLASS 4+4 (TRAPEZOID, v1 MEASURED)"
  line L0 (-961, -105) -> (214, -105)
  line L1 (214, -105) -> (-68, -2116)
  line L2 (-68, -2116) -> (-961, -2116)
  line L3 (-961, -2116) -> (-961, -105)
  dimension "d343" = 214
  dimension "d344" = 68
  dimension "d345" = 961
  dimension "d346" = 105
  dimension "d347" = 2116
  constraint vertical L3
  constraint horizontal L0
  constraint horizontal L2
  measures "d343" horizontal distance of origin L0.end
  measures "d344" horizontal distance of origin L1.end
  measures "d345" horizontal distance of origin L2.end
  measures "d346" vertical distance of origin L0.start
  measures "d347" vertical distance of origin L1.end
extrude "EXTRUDE - DOOR GLASS" add sketch "OUTLINE - DOOR" along normal blind 8.76 from surface at -703.38 separate body makes body 26 in component "DOOR FRONT - DOOR LEAF GLASS 4+4 (TRAPEZOID, v1 MEASURED)"
sketch "OUTLINE - FIXED" plane through (0, 0, 0) normal (0, 1, 0) x (1, 0, 0) in component "FIXED FRONT - FIXED GLASS 4+4 (PENTAGON, v1 MEASURED)"
  line L0 (218.4598, -102) -> (948, -102)
  line L1 (948, -102) -> (749, -1521)
  line L2 (749, -1521) -> (230, -2119)
  line L3 (230, -2119) -> (-64.3815, -2119)
  line L4 (-64.3815, -2119) -> (218.4598, -102)
  dimension "d351" = 218.4598
  dimension "d352" = 948
  dimension "d353" = 749
  dimension "d354" = 230
  dimension "d355" = 64.3815
  dimension "d356" = 102
  dimension "d357" = 1521
  dimension "d358" = 2119
  constraint horizontal L0
  constraint horizontal L3
  measures "d351" horizontal distance of origin L0.start
  measures "d352" horizontal distance of origin L0.end
  measures "d353" horizontal distance of origin L1.end
  measures "d354" horizontal distance of origin L2.end
  measures "d355" horizontal distance of origin L3.end
  measures "d356" vertical distance of origin L0.start
  measures "d357" vertical distance of origin L1.end
  measures "d358" vertical distance of origin L2.end
extrude "EXTRUDE - FIXED GLASS" add sketch "OUTLINE - FIXED" along normal blind 8.76 from surface at -703.38 separate body makes body 27 in component "FIXED FRONT - FIXED GLASS 4+4 (PENTAGON, v1 MEASURED)"
sketch "PLAN - BAND-L" plane through (0, 0, 0) normal (0, 0, 1) x (1, 0, 0) in component "BAND-L BASE - BASE BAND - SIDE - LH"
  line L0 (-1250, -670) -> (-1250, 850)
  line L1 (-1250, 850) -> (-1210, 850)
  line L2 (-1210, 850) -> (-1210, -652.0697)
  line L3 (-1210, -652.0697) -> (-1250, -670)
  dimension "d362" = 1250
  dimension "d363" = 1210
  dimension "d364" = 670
  dimension "d365" = 850
  dimension "d366" = 652.0697
  constraint vertical L0
  constraint vertical L2
  constraint horizontal L1
  measures "d362" horizontal distance of origin L0.start
  measures "d363" horizontal distance of origin L1.end
  measures "d364" vertical distance of origin L0.start
  measures "d365" vertical distance of origin L0.end
  measures "d366" vertical distance of origin L2.end
extrude "EXTRUDE - BAND-L" add sketch "PLAN - BAND-L" along normal blind 100 from surface at 10 separate body makes body 28 in component "BAND-L BASE - BASE BAND - SIDE - LH"
sketch "PLAN - BAND-FL" plane through (0, 0, 0) normal (0, 0, 1) x (1, 0, 0) in component "BAND-FL BASE - BASE BAND - FRONT LEFT (FACETED, UNDER DL)"
  line L0 (-1250, -670) -> (-1158, -752)
  line L1 (-1158, -752) -> (-979, -844)
  line L2 (-979, -844) -> (-972, -844)
  line L3 (-972, -844) -> (-972, -802.6238)
  line L4 (-972, -802.6238) -> (-1135.1863, -718.7515)
  line L5 (-1135.1863, -718.7515) -> (-1210, -652.0697)
  line L6 (-1210, -652.0697) -> (-1250, -670)
  dimension "d370" = 1250
  dimension "d371" = 1158
  dimension "d372" = 979
  dimension "d373" = 972
  dimension "d374" = 1135.1863
  dimension "d375" = 1210
  dimension "d376" = 670
  dimension "d377" = 752
  dimension "d378" = 844
  dimension "d379" = 802.6238
  dimension "d380" = 718.7515
  dimension "d381" = 652.0697
  constraint vertical L3
  constraint horizontal L2
  measures "d370" horizontal distance of origin L0.start
  measures "d371" horizontal distance of origin L0.end
  measures "d372" horizontal distance of origin L1.end
  measures "d373" horizontal distance of origin L2.end
  measures "d374" horizontal distance of origin L4.end
  measures "d375" horizontal distance of origin L5.end
  measures "d376" vertical distance of origin L0.start
  measures "d377" vertical distance of origin L0.end
  measures "d378" vertical distance of origin L1.end
  measures "d379" vertical distance of origin L3.end
  measures "d380" vertical distance of origin L4.end
  measures "d381" vertical distance of origin L5.end
extrude "EXTRUDE - BAND-FL" add sketch "PLAN - BAND-FL" along normal blind 100 from surface at 10 separate body makes body 29 in component "BAND-FL BASE - BASE BAND - FRONT LEFT (FACETED, UNDER DL)"
sketch "PLAN - BAND-FR" plane through (0, 0, 0) normal (0, 0, 1) x (1, 0, 0) in component "BAND-FR BASE - BASE BAND - FRONT RIGHT (FACETED, UNDER THE FIXED GLASS AND DR)"
  line L0 (218.4598, -850) -> (1052, -850)
  line L1 (1052, -850) -> (1250, -672)
  line L2 (1250, -672) -> (1210, -654.1721)
  line L3 (1210, -654.1721) -> (1036.6634, -810)
  line L4 (1036.6634, -810) -> (218.4598, -810)
  line L5 (218.4598, -810) -> (218.4598, -850)
  dimension "d385" = 1052
  dimension "d386" = 1250
  dimension "d387" = 1210
  dimension "d388" = 1036.6634
  dimension "d389" = 218.4598
  dimension "d390" = 850
  dimension "d391" = 672
  dimension "d392" = 654.1721
  dimension "d393" = 810
  constraint vertical L5
  constraint horizontal L0
  constraint horizontal L4
  measures "d385" horizontal distance of origin L0.end
  measures "d386" horizontal distance of origin L1.end
  measures "d387" horizontal distance of origin L2.end
  measures "d388" horizontal distance of origin L3.end
  measures "d389" horizontal distance of origin L4.end
  measures "d390" vertical distance of origin L0.start
  measures "d391" vertical distance of origin L1.end
  measures "d392" vertical distance of origin L2.end
  measures "d393" vertical distance of origin L3.end
extrude "EXTRUDE - BAND-FR" add sketch "PLAN - BAND-FR" along normal blind 100 from surface at 10 separate body makes body 30 in component "BAND-FR BASE - BASE BAND - FRONT RIGHT (FACETED, UNDER THE FIXED GLASS AND DR)"
sketch "PLAN - BAND-R" plane through (0, 0, 0) normal (0, 0, 1) x (1, 0, 0) in component "BAND-R BASE - BASE BAND - SIDE - RH"
  line L0 (1250, -672) -> (1250, 850)
  line L1 (1250, 850) -> (1210, 850)
  line L2 (1210, 850) -> (1210, -654.1721)
  line L3 (1210, -654.1721) -> (1250, -672)
  dimension "d397" = 1250
  dimension "d398" = 1210
  dimension "d399" = 672
  dimension "d400" = 850
  dimension "d401" = 654.1721
  constraint vertical L0
  constraint vertical L2
  constraint horizontal L1
  measures "d397" horizontal distance of origin L0.start
  measures "d398" horizontal distance of origin L1.end
  measures "d399" vertical distance of origin L0.start
  measures "d400" vertical distance of origin L0.end
  measures "d401" vertical distance of origin L2.end
extrude "EXTRUDE - BAND-R" add sketch "PLAN - BAND-R" along normal blind 100 from surface at 10 separate body makes body 31 in component "BAND-R BASE - BASE BAND - SIDE - RH"
component "110000 BASE" placed x (1, 0, 0) y (0, 1, 0) z (0, 0, 1) at (0, 0, 0)
component "210000 WALL" placed x (1, 0, 0) y (0, 1, 0) z (0, 0, 1) at (0, 0, 0)
component "350000 FRONT" placed x (1, 0, 0) y (0, 1, 0) z (0, 0, 1) at (0, 0, 0)
component "410000 CEILING" placed x (1, 0, 0) y (0, 1, 0) z (0, 0, 1) at (0, 0, 0)
component "510000 LINING" placed x (1, 0, 0) y (0, 1, 0) z (0, 0, 1) at (0, 0, 0)
component "610000 AIR" placed x (1, 0, 0) y (0, 1, 0) z (0, 0, 1) at (0, 0, 0)
component "710000 ELECTRICAL" placed x (1, 0, 0) y (0, 1, 0) z (0, 0, 1) at (0, 0, 0)
component "810000 INTERIOR" placed x (1, 0, 0) y (0, 1, 0) z (0, 0, 1) at (0, 0, 0)
component "BAND-BACK BASE - BASE BAND - BACK" placed x (1, 0, 0) y (0, 1, 0) z (0, 0, 1) at (0, 0, 0) in component "110000 BASE"
component "BAND-L BASE - BASE BAND - SIDE - LH" placed x (1, 0, 0) y (0, 1, 0) z (0, 0, 1) at (0, 0, 0) in component "110000 BASE"
component "BAND-FL BASE - BASE BAND - FRONT LEFT (FACETED, UNDER DL)" placed x (1, 0, 0) y (0, 1, 0) z (0, 0, 1) at (0, 0, 0) in component "110000 BASE"
component "BAND-FR BASE - BASE BAND - FRONT RIGHT (FACETED, UNDER THE FIXED GLASS AND DR)" placed x (1, 0, 0) y (0, 1, 0) z (0, 0, 1) at (0, 0, 0) in component "110000 BASE"
component "BAND-R BASE - BASE BAND - SIDE - RH" placed x (1, 0, 0) y (0, 1, 0) z (0, 0, 1) at (0, 0, 0) in component "110000 BASE"
component "L1 WALL - SIDE PANEL - LOWER - LH" placed x (1, 0, 0) y (0, 1, 0) z (0, 0, 1) at (0, 0, 0) in component "210000 WALL"
component "L2 WALL - SIDE PANEL - UPPER - LH" placed x (1, 0, 0) y (0, 1, 0) z (0, 0, 1) at (0, 0, 0) in component "210000 WALL"
component "R1 WALL - SIDE PANEL - LOWER - RH" placed x (1, 0, 0) y (0, 1, 0) z (0, 0, 1) at (0, 0, 0) in component "210000 WALL"
component "R2 WALL - SIDE PANEL - UPPER - RH" placed x (1, 0, 0) y (0, 1, 0) z (0, 0, 1) at (0, 0, 0) in component "210000 WALL"
component "B1 WALL - BACK PANEL - LOWER - B1" placed x (1, 0, 0) y (0, 1, 0) z (0, 0, 1) at (0, 0, 0) in component "210000 WALL"
component "B2 WALL - BACK PANEL - LOWER - B2" placed x (1, 0, 0) y (0, 1, 0) z (0, 0, 1) at (0, 0, 0) in component "210000 WALL"
component "B3 WALL - BACK PANEL - UPPER - B3" placed x (1, 0, 0) y (0, 1, 0) z (0, 0, 1) at (0, 0, 0) in component "210000 WALL"
component "B4 WALL - BACK PANEL - UPPER - B4" placed x (1, 0, 0) y (0, 1, 0) z (0, 0, 1) at (0, 0, 0) in component "210000 WALL"
component "360000 FRONT - DOOR AND GLAZING" placed x (1, 0, 0) y (0, 1, 0) z (0, 0, 1) at (0, 0, 0) in component "350000 FRONT"
component "DL FRONT - DECOR BLOCK - LEFT (FACETED, v1 MEASURED)" placed x (1, 0, 0) y (0, 1, 0) z (0, 0, 1) at (0, 0, 0) in component "350000 FRONT"
component "DT FRONT - DECOR BLOCK - TOP (FACETED, v1 MEASURED)" placed x (1, 0, 0) y (0, 1, 0) z (0, 0, 1) at (0, 0, 0) in component "350000 FRONT"
component "DR FRONT - DECOR BLOCK - RIGHT (FACETED, v1 MEASURED)" placed x (1, 0, 0) y (0, 1, 0) z (0, 0, 1) at (0, 0, 0) in component "350000 FRONT"
component "KICK FRONT - DOOR KICK STRIP" placed x (1, 0, 0) y (0, 1, 0) z (0, 0, 1) at (0, 0, 0) in component "360000 FRONT - DOOR AND GLAZING"
component "DOOR FRONT - DOOR LEAF GLASS 4+4 (TRAPEZOID, v1 MEASURED)" placed x (1, 0, 0) y (0, 1, 0) z (0, 0, 1) at (0, 0, 0) in component "360000 FRONT - DOOR AND GLAZING"
component "FIXED FRONT - FIXED GLASS 4+4 (PENTAGON, v1 MEASURED)" placed x (1, 0, 0) y (0, 1, 0) z (0, 0, 1) at (0, 0, 0) in component "360000 FRONT - DOOR AND GLAZING"
component "C1 CEILING - HALF PANEL - C1" placed x (1, 0, 0) y (0, 1, 0) z (0, 0, 1) at (0, 0, 0) in component "410000 CEILING"
component "C2 CEILING - HALF PANEL - C2" placed x (1, 0, 0) y (0, 1, 0) z (0, 0, 1) at (0, 0, 0) in component "410000 CEILING"
component "L1-CASS LINING - CASSETTE - SIDE LOWER - L" placed x (1, 0, 0) y (0, 1, 0) z (0, 0, 1) at (0, 0, 0) in component "510000 LINING"
component "L2-CASS LINING - CASSETTE - SIDE UPPER - L" placed x (1, 0, 0) y (0, 1, 0) z (0, 0, 1) at (0, 0, 0) in component "510000 LINING"
component "R1-CASS LINING - CASSETTE - SIDE LOWER - R" placed x (1, 0, 0) y (0, 1, 0) z (0, 0, 1) at (0, 0, 0) in component "510000 LINING"
component "R2-CASS LINING - CASSETTE - SIDE UPPER - R" placed x (1, 0, 0) y (0, 1, 0) z (0, 0, 1) at (0, 0, 0) in component "510000 LINING"
component "B1-CASS LINING - CASSETTE - BACK LOWER - B1" placed x (1, 0, 0) y (0, 1, 0) z (0, 0, 1) at (0, 0, 0) in component "510000 LINING"
component "B2-CASS LINING - CASSETTE - BACK LOWER - B2" placed x (1, 0, 0) y (0, 1, 0) z (0, 0, 1) at (0, 0, 0) in component "510000 LINING"
component "B3-CASS LINING - CASSETTE - BACK UPPER - B3" placed x (1, 0, 0) y (0, 1, 0) z (0, 0, 1) at (0, 0, 0) in component "510000 LINING"
component "B4-CASS LINING - CASSETTE - BACK UPPER - B4" placed x (1, 0, 0) y (0, 1, 0) z (0, 0, 1) at (0, 0, 0) in component "510000 LINING"
component "C1-CASS LINING - CASSETTE - CEILING - C1" placed x (1, 0, 0) y (0, 1, 0) z (0, 0, 1) at (0, 0, 0) in component "510000 LINING"
component "C2-CASS LINING - CASSETTE - CEILING - C2" placed x (1, 0, 0) y (0, 1, 0) z (0, 0, 1) at (0, 0, 0) in component "510000 LINING"
equation "pod_w = 2500 mm" comment "DECIDED: D-01; conventions s4 (X = +-1250)"
equation "pod_d = 1700 mm" comment "DECIDED: D-01; conventions s4 (Y = +-850)"
equation "pod_h = 2400 mm" comment "DECIDED: D-21 (room floor to roof skin top)"
equation "glide_h = 10 mm" comment "ASSUMPTION: layout study inputs.py glide_h"
equation "band_h = 100 mm" comment "SOURCE: layout study B1 list B-BAND 100x40; inputs.py base_h"
equation "band_t = 40 mm" comment "SOURCE: layout study B1 list B-BAND 100x40"